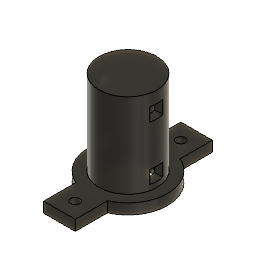
02_centered_brush_cartridge_15mm_editable (Autodesk Fusion 360 design; units mm, degrees)
part number: 2026-10-21-19-44-37-601
Autodesk Fusion 360 part; units mm, degrees
ref_plane "作業平面1" through (0, 0, -26.5) normal (0, 0, 1) x (1, 0, 0)
sketch "スケッチ1" plane through (0, 0, -26.5) normal (0, 0, 1) x (1, 0, 0)
  circle A0 centre (30, 2.7629) radius 15
  dimension "d1041" = 30
  measures "d1041" diameter of A0
extrude "V4_flat_cartridge_flange" add sketch "スケッチ1" along normal blind 4
ref_plane "作業平面2" through (0, 0, -26.5) normal (0, 0, 1) x (1, 0, 0)
sketch "スケッチ2" plane through (0, 0, -26.5) normal (0, 0, 1) x (1, 0, 0)
  line L0 (24, -23.2371) -> (36, -23.2371)
  line L1 (36, -23.2371) -> (36, -10.2371)
  line L2 (36, -10.2371) -> (24, -10.2371)
  line L3 (24, -10.2371) -> (24, -23.2371)
extrude "V4_cartridge_flange_ear_-1 (1)" add sketch "スケッチ2" along normal blind 4
ref_plane "作業平面3" through (0, 0, -26.5) normal (0, 0, 1) x (1, 0, 0)
sketch "スケッチ3" plane through (0, 0, -26.5) normal (0, 0, 1) x (1, 0, 0)
  line L0 (24, 15.7629) -> (36, 15.7629)
  line L1 (36, 15.7629) -> (36, 28.7629)
  line L2 (36, 28.7629) -> (24, 28.7629)
  line L3 (24, 28.7629) -> (24, 15.7629)
extrude "V4_cartridge_flange_ear_1 (1)" add sketch "スケッチ3" along normal blind 4
ref_plane "作業平面4" through (0, 0, -26.5) normal (0, 0, 1) x (1, 0, 0)
sketch "スケッチ4" plane through (0, 0, -26.5) normal (0, 0, 1) x (1, 0, 0)
  circle A0 centre (30, 2.7629) radius 11
  dimension "d1054" = 22
  measures "d1054" diameter of A0
extrude "V4_cartridge_vertical_sleeve" add sketch "スケッチ4" along normal blind 36
ref_plane "作業平面5" through (0, 0, -26.5) normal (0, 0, 1) x (1, 0, 0)
sketch "スケッチ5" plane through (0, 0, -26.5) normal (0, 0, 1) x (1, 0, 0)
  circle A0 centre (30, 2.7629) radius 8
  dimension "d1059" = 16
  measures "d1059" diameter of A0
extrude "V4_parameterized_blind_bore" cut sketch "スケッチ5" along normal blind 34
ref_plane "作業平面6" through (0, 0, -26.5) normal (0, 0, 1) x (1, 0, 0)
sketch "スケッチ6" plane through (0, 0, -26.5) normal (0, 0, 1) x (1, 0, 0)
  circle A0 centre (30, 2.7629) radius 11
  dimension "d1064" = 22
  measures "d1064" diameter of A0
extrude "V4_centering_land_-26.5" add sketch "スケッチ6" along normal blind 2
ref_plane "作業平面7" through (0, 0, -26.5) normal (0, 0, 1) x (1, 0, 0)
sketch "スケッチ7" plane through (0, 0, -26.5) normal (0, 0, 1) x (1, 0, 0)
  circle A0 centre (30, 2.7629) radius 7.7
  dimension "d1069" = 15.4
  measures "d1069" diameter of A0
extrude "V4_non_clamping_brush_guide_-26.5" cut sketch "スケッチ7" along normal blind 2
ref_plane "作業平面8" through (0, 0, 5.5) normal (0, 0, 1) x (1, 0, 0)
sketch "スケッチ8" plane through (0, 0, 5.5) normal (0, 0, 1) x (1, 0, 0)
  circle A0 centre (30, 2.7629) radius 11
  dimension "d1074" = 22
  measures "d1074" diameter of A0
extrude "V4_centering_land_5.5" add sketch "スケッチ8" along normal blind 2
ref_plane "作業平面9" through (0, 0, 5.5) normal (0, 0, 1) x (1, 0, 0)
sketch "スケッチ9" plane through (0, 0, 5.5) normal (0, 0, 1) x (1, 0, 0)
  circle A0 centre (30, 2.7629) radius 7.7
  dimension "d1079" = 15.4
  measures "d1079" diameter of A0
extrude "V4_non_clamping_brush_guide_5.5" cut sketch "スケッチ9" along normal blind 2
ref_plane "作業平面10" through (0, 0, -26.5) normal (0, 0, 1) x (1, 0, 0)
sketch "スケッチ10" plane through (0, 0, -26.5) normal (0, 0, 1) x (1, 0, 0)
  circle A0 centre (30, -17.2371) radius 1.7
  circle A1 centre (30, 22.7629) radius 1.7
  dimension "d1084" = 3.4
  dimension "d1085" = 3.4
  measures "d1084" diameter of A0
  measures "d1085" diameter of A1
extrude "V4_cartridge_M3_clearance" cut sketch "スケッチ10" along normal blind 4
ref_plane "作業平面11" through (17, 0, 0) normal (1, 0, 0) x (0, 1, 0)
sketch "スケッチ11" plane through (17, 0, 0) normal (1, 0, 0) x (0, 0, -1)
  line L0 (20.5, 0.2629) -> (20.5, 5.2629)
  line L1 (20.5, 5.2629) -> (15.5, 5.2629)
  line L2 (15.5, 5.2629) -> (15.5, 0.2629)
  line L3 (15.5, 0.2629) -> (20.5, 0.2629)
extrude "V4_hot_glue_key_windows_-20.5" cut sketch "スケッチ11" along normal blind 26
ref_plane "作業平面12" through (17, 0, 0) normal (1, 0, 0) x (0, 1, 0)
sketch "スケッチ12" plane through (17, 0, 0) normal (1, 0, 0) x (0, 0, -1)
  line L0 (0, 0.2629) -> (0, 5.2629)
  line L1 (0, 5.2629) -> (-5, 5.2629)
  line L2 (-5, 5.2629) -> (-5, 0.2629)
  line L3 (-5, 0.2629) -> (0, 0.2629)
extrude "V4_hot_glue_key_windows_0.0" cut sketch "スケッチ12" along normal blind 26
equation "d1041 = brush_flange_od"
equation "d1042 = brush_flange_thickness"
equation "d1046 = brush_flange_thickness"
equation "d1050 = brush_flange_thickness"
equation "d1054 = brush_cartridge_od"
equation "d1055 = brush_sleeve_length"
equation "d1059 = brush_cartridge_id"
equation "d1060 = brush_sleeve_length - centered_brush_cap_thickness"
equation "d1064 = brush_cartridge_od"
equation "d1069 = brush_guide_dia"
equation "d1074 = brush_cartridge_od"
equation "d1079 = brush_guide_dia"
equation "d1084 = sc_screw_clearance"
equation "d1085 = sc_screw_clearance"
equation "d1086 = brush_flange_thickness"
equation "brush_dia = 15 mm" comment "ç­è»¸ã®ç´å¾ â å®æ¸¬"
equation "sc_screw_clearance = 3.4 mm" comment "Printed base M3 clearance; sensor itself has M3 threaded holes"
equation "brush_glue_allowance = 1.0 mm" comment "Diametral allowance for hot glue around brush"
equation "brush_cartridge_od = 22 mm" comment "Rigid sleeve outside diameter; nominal wall 3 mm"
equation "brush_cartridge_id = brush_dia + brush_glue_allowance" comment "Nominal brush bore"
equation "brush_flange_od = brush_cartridge_od + 8 mm" comment "Cartridge load-bearing flange diameter"
equation "brush_sleeve_length = 36 mm" comment "Length of replaceable glued brush sleeve"
equation "brush_flange_thickness = 4 mm" comment "Cartridge flange thickness"
equation "brush_guide_dia = brush_dia + 0.4 mm" comment "Slip guide at both sleeve ends; no clamp or interference fit"
equation "centered_brush_cap_thickness = 2 mm" comment "Closed upper cap transfers axial brush force to moving carrier only"
named bodies: "Centered_15mm_Hot_Glue_Cartridge_With_Stop"
